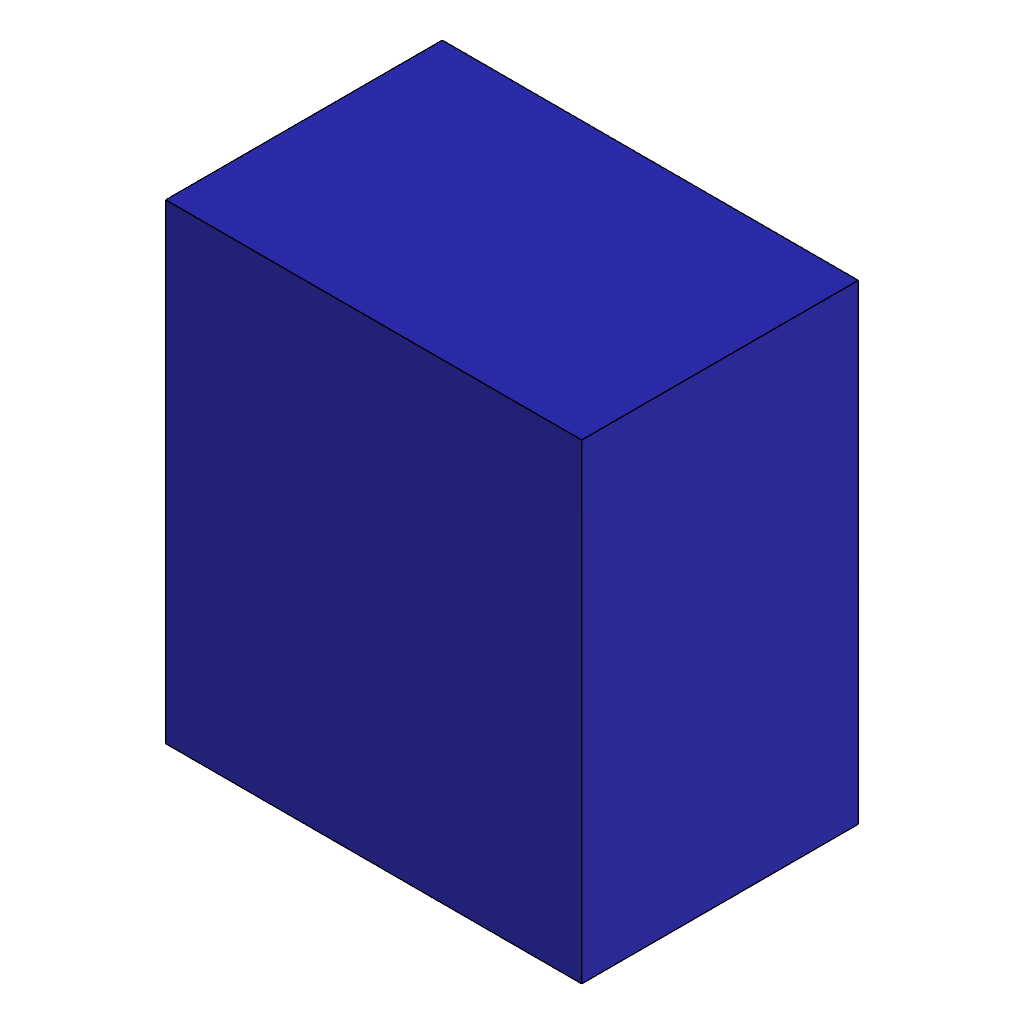
GeneratedResaveEdited (Autodesk Fusion 360 design; units mm, degrees)
Autodesk Fusion 360 part; units mm, degrees
sketch "Slate Gauge Rectangle" plane through (0, 0, 0) normal (0, 0, 1) x (1, 0, 0)
  line L0 (0, 0) -> (24.625, 0)
  line L1 (24.625, 0) -> (24.625, 16.375)
  line L2 (24.625, 16.375) -> (0, 16.375)
  line L3 (0, 16.375) -> (0, 0)
  dimension "widthModel" = 24.625
  dimension "depthModel" = 16.375
  constraint horizontal L0
  constraint vertical L1
  constraint horizontal L2
  constraint vertical L3
  measures "widthModel" horizontal distance of L0.start L0.end
  measures "depthModel" vertical distance of L0.start L2.end
extrude "Slate Gauge Extrusion" add sketch "Slate Gauge Rectangle" along normal blind 27.875
equation "riseGauge = 27.875 mm" comment "Drives the height of the held profile"
equation "heightModel = riseGauge"
equation "draftAngle = 0 deg"
equation "widthGauge = 24.625 mm" comment "Drives the width of the held profile"
equation "depthGauge = 16.375 mm" comment "Drives the depth of the held profile"
equation "widthModel = widthGauge"
equation "depthModel = depthGauge"
